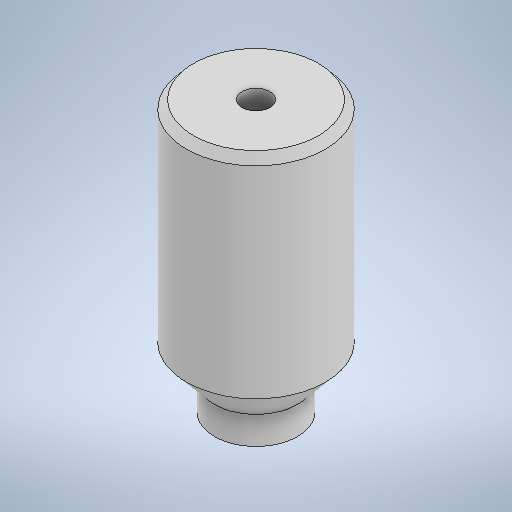
# Autodesk Inventor part: mango_3
Saved by Autodesk Inventor 2025.2 (Build 292293000, 293)
## iProperties
Created: 2025-03-19
Part Number: mango_3
Material: Generic
Document SubType Name: Modeling
Designer: laura
Density: 1 g/cm^3
Appearance: Default
Author: laura
Autodesk Inventor part; units mm, degrees
ref_plane "YZ Plane" through (0, 0, 0) normal (1, 0, 0) x (0, 1, 0)
ref_plane "XZ Plane" through (0, 0, 0) normal (0, 1, 0) x (-1, 0, 0)
ref_plane "XY Plane" through (0, 0, 0) normal (0, 0, 1) x (1, 0, 0)
sketch "Sketch1" plane through (0, 0, 0) normal (0, 0, 1) x (1, 0, 0)
  line L0 (10, 33.8082) -> (9, 35)
  line L1 (9, 35) -> (0, 35)
  line L2 (6, 0) -> (0, 0) construction
  line L3 (0, 0) -> (0, 35)
  line L4 (6, 0) -> (6, -4)
  line L5 (6, -4) -> (0, -4)
  line L6 (0, -4) -> (0, 0)
  line L7 (10, 33.8082) -> (10, 4.767)
  line L8 (10, 4.767) -> (6, 0)
  dimension "d0" = 35
  dimension "d1" = 18
  dimension "d2" = 20
  dimension "d3" = 6
  dimension "d9" = 4
  dimension "d15" = 50
  dimension "d16" = 50
  constraints: 19 end point, 3 vertical, 2 horizontal, 2 perpendicular
  measures "d0" distance of L2.end L1.end
  measures "d1" diameter of L0.end L3
  measures "d2" diameter of L0.start L3
  measures "d3" distance of L2.end L2.start
  measures "d9" distance of L2.start L4.end
  measures "d15" angle of L2 L8
  measures "d16" angle of L1 L0
revolve "Revolution1" add sketch "Sketch1" angle 360 about axis through (0, 0, 0) along (0, 1, 0)
sketch "Sketch2" plane through (0, -4, 0) normal (0, -1, 0) x (1, 0, 0)
  circle A0 centre (0, 0) radius 2
  point P0 (0, 0)
  dimension "d12" = 4
  constraints: 1 centre point, 1 coincident
  measures "d12" diameter of A0
extrude "Extrusion1" cut sketch "Sketch2" against normal through all
body "Solid1"
